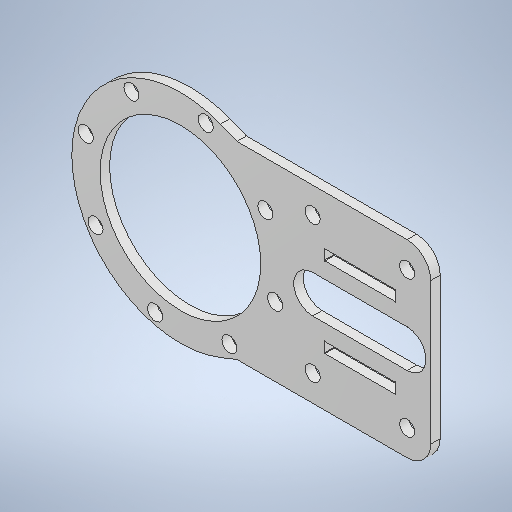
# Autodesk Inventor part: 3dp_pMount
Saved by Autodesk Inventor 2025.3 (Build 293356000, 356)
## iProperties
Created: 2026-10-04
Part Number: 3dp_pMount
Material: アルミニウム 5052 H32
Document SubType Name: Modeling
Designer: yunto
Density: 2.68 g/cm^3
Appearance: サテン
Author: yunto
Autodesk Inventor part; units mm, degrees
ref_plane "YZ Plane" through (0, 0, 0) normal (1, 0, 0) x (0, 1, 0)
ref_plane "XZ Plane" through (0, 0, 0) normal (0, 1, 0) x (-1, 0, 0)
ref_plane "XY Plane" through (0, 0, 0) normal (0, 0, 1) x (1, 0, 0)
sketch "スケッチ1" plane through (0, 0, 0) normal (0, 0, 1) x (1, 0, 0)
  circle A0 centre (0, 0) radius 23
  circle A1 centre (0, 0) radius 17
  circle A2 centre (-10.375, 17.97) radius 1.6
  line L0 (-10.375, 17.97) -> (0, 0) construction
  circle A3 centre (-20.043, 5.3705) radius 1.6
  circle A4 centre (-17.97, -10.375) radius 1.6
  circle A5 centre (-5.3705, -20.043) radius 1.6
  circle A6 centre (10.375, -17.97) radius 1.6
  circle A7 centre (20.043, -5.3705) radius 1.6
  circle A8 centre (17.97, 10.375) radius 1.6
  circle A9 centre (5.3705, 20.043) radius 1.6
  line L1 (11.3578, 20) -> (53, 20)
  line L2 (53, 20) -> (53, -20)
  line L3 (53, -20) -> (11.3578, -20)
  line L4 (40, 0) -> (60, 0) construction
  line L5 (8.4523, -21.3906) -> (11.9716, -20)
  line L6 (8.4523, 21.3906) -> (11.9716, 20)
  line L7 (-23, 0) -> (-23, 0)
  line L8 (0, 23) -> (0, 0) construction
  line L9 (48, -14.5) -> (28, -14.5) construction
  line L10 (28, -14.5) -> (28, 14.5) construction
  line L11 (28, 14.5) -> (48, 14.5) construction
  line L12 (48, 14.5) -> (48, -14.5) construction
  line L13 (48, -14.5) -> (28, 14.5) construction
  line L14 (28, -14.5) -> (48, 14.5) construction
  circle A10 centre (28, 14.5) radius 1.6
  circle A11 centre (48, 14.5) radius 1.6
  circle A12 centre (48, -14.5) radius 1.6
  circle A13 centre (28, -14.5) radius 1.6
  line L15 (45.5, 7.4) -> (30.5, 7.4)
  line L16 (30.5, 7.4) -> (30.5, 9.6)
  line L17 (30.5, 9.6) -> (45.5, 9.6)
  line L18 (45.5, 9.6) -> (45.5, 7.4)
  line L19 (45.5, 7.4) -> (30.5, 9.6) construction
  line L20 (30.5, 7.4) -> (45.5, 9.6) construction
  line L21 (38, 8.5) -> (38, 0) construction
  line L22 (45.5, -7.4) -> (30.5, -7.4)
  line L23 (30.5, -7.4) -> (30.5, -9.6)
  line L24 (30.5, -9.6) -> (45.5, -9.6)
  line L25 (45.5, -9.6) -> (45.5, -7.4)
  line L26 (45.5, -7.4) -> (30.5, -9.6) construction
  line L27 (30.5, -7.4) -> (45.5, -9.6) construction
  circle A14 centre (28, 0) radius 4
  circle A15 centre (48, 0) radius 4
  circle A16 centre (30.5, 9.6) radius 0.1
  circle A17 centre (30.5, 7.4) radius 0.1
  circle A18 centre (45.5, 7.4) radius 0.1
  circle A19 centre (45.5, 9.6) radius 0.1
  circle A20 centre (30.5, -7.4) radius 0.1
  circle A21 centre (30.5, -9.6) radius 0.1
  circle A22 centre (45.5, -9.6) radius 0.1
  circle A23 centre (45.5, -7.4) radius 0.1
  line L28 (28, 4) -> (48, 4)
  line L29 (48, -4) -> (28, -4)
  point P0 (50, 0)
  point P1 (8.4523, 21.3906)
  point P2 (38, -8.5)
  point P3 (45.5, -7.5)
  point P4 (45.5, -9.5)
  point P5 (45.4, -9.6)
  point P6 (30.6, -9.6)
  point P7 (30.5, -9.5)
  point P8 (30.5, -7.5)
  point P9 (30.6, -7.4)
  point P10 (45.4, -7.4)
  point P11 (45.5, 9.5)
  point P12 (45.5, 7.5)
  point P13 (45.4, 7.4)
  point P14 (30.6, 7.4)
  point P15 (30.5, 7.5)
  point P16 (30.5, 9.5)
  point P17 (30.6, 9.6)
  point P18 (45.4, 9.6)
  dimension "d0" = 34
  dimension "d1" = 46
  dimension "d2" = 20.75
  dimension "d3" = 3.2
  dimension "d6" = 360
  dimension "d9" = 40
  dimension "d16" = 20
  dimension "d19" = 40
  dimension "d26" = 23
  dimension "d27" = 30
  dimension "d28" = 3.2
  dimension "d29" = 20
  dimension "d30" = 29
  dimension "d31" = 5
  dimension "d32" = 38
  dimension "d33" = 2.2
  dimension "d34" = 15
  dimension "d35" = 8.5
  dimension "d36" = 8
  dimension "d37" = 0.2
  constraints: 60 end point, 24 centre point, 15 coincident, 11 equal radius, 10 point on circle, 7 midpoint, 7 point on line, 7 symmetric about line, 4 horizontal, 4 parallel, 4 vertical, 3 perpendicular, 1 tangent, 18 other
  measures "d0" diameter of A1
  measures "d1" diameter of A0
  measures "d2" distance of L0.start L0.end
  measures "d3" diameter of A2
  measures "d9" distance of L1.end L2.end
  measures "d16" distance of L4.start L4.end
  measures "d19" distance of point (0, 0) L4.start
  measures "d26" distance from line of point (0, 0) L7
  measures "d27" angle of L0 L8
  measures "d28" diameter of A10
  measures "d29" distance of L10.end L11.end
  measures "d30" distance of L11.end L13.start
  measures "d31" distance between parallel lines of L2 L12
  measures "d32" distance of point (38, 0) A0.centre
  measures "d33" distance of L15.end L16.end
  measures "d34" distance of L16.end L17.end
  measures "d35" distance of L21.start L21.end
  measures "d36" diameter of A14
  measures "d37" diameter of A16
extrude "押し出し1" add sketch "スケッチ1" along normal blind 2
extrude "押し出し2" [suppressed]
fillet "フィレット1" radius 5 2 edges at (53, -20, 1) (53, 20, 1)
equation "\"d27\" = pRSdeg"
equation "\"pitchLength\" = 65"
equation "\"pRSdeg\" = 30deg"
equation "\"handDeg\" = 60deg"
